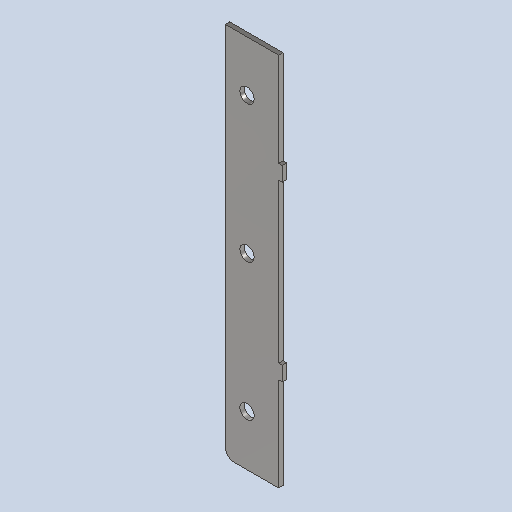
# Autodesk Inventor part: DMF-1214 Slot spoke 1
Saved by Autodesk Inventor 2026.2 (Build 302298000, 298)
## iProperties
Created: 2024-04-30
Part Number: DMF-1214 Slot spoke 1
Material: Stainless Steel
Document SubType Name: Sheet Metal
Designer: admin
Stock Number: DMF-1214
Mass: 30.2951 g
Surface Area: 223.238 cm^2
Volume: 30.2951 cm^3
Density: 8 g/cm^3
Flat Pattern Width: 3.95 cm
Flat Pattern Length: 26 cm
Flat Pattern Area: 102.7 cm^2
Sheet Metal Rule: Default
Sheet Metal Width: 39,500 mm
Sheet Metal Length: 260,000 mm
Sheet Metal Area: 10270,000 mm^2
Appearance: Semi-Polished
Author: pokla
Autodesk Inventor part; units mm, degrees
ref_plane "YZ Plane" through (0, 0, 0) normal (1, 0, 0) x (0, 1, 0)
ref_plane "XZ Plane" through (0, 0, 0) normal (0, 1, 0) x (-1, 0, 0)
ref_plane "XY Plane" through (0, 0, 0) normal (0, 0, 1) x (1, 0, 0)
sketch "Sketch1" plane through (0, 0, 0) normal (0, 0, 1) x (1, 0, 0)
  line L0 (0, 130) -> (0, -130)
  line L1 (0, -130) -> (-37, -130)
  line L2 (-37, -130) -> (-37, 130)
  line L3 (-37, 130) -> (0, 130)
  line L4 (-37, 0) -> (0, 0) construction
  line L5 (0, 65) -> (2.5, 65)
  line L6 (2.5, 65) -> (2.5, 55)
  line L7 (2.5, 55) -> (0, 55)
  line L8 (0, 55) -> (0, 65)
  line L9 (0, -55) -> (2.5, -55)
  line L10 (2.5, -55) -> (2.5, -65)
  line L11 (2.5, -65) -> (0, -65)
  line L12 (0, -65) -> (0, -55)
  circle A0 centre (-22, 95) radius 5
  circle A1 centre (-22, 0) radius 5
  circle A2 centre (-22, -95) radius 5
  point P0 (2.5, -60)
  point P1 (2.5, 60)
  dimension "d106" = 37
  dimension "d107" = 260
  dimension "d108" = 2.5
  dimension "d109" = 10
  dimension "d110" = 120
  dimension "d112" = 10
  dimension "d113" = 190
  dimension "d114" = 15
  measures "d106" distance of L2.end L0.start
  measures "d107" distance of L1.end L2.end
  measures "d108" distance of L6.end L7.end
  measures "d109" distance of L5.end L6.end
  measures "d110" distance of point (2.5, -60) point (2.5, 60)
  measures "d112" diameter of A1
  measures "d113" distance of A2.centre A0.centre
  measures "d114" distance from line of L2 A1.centre
extrude "Plate1" add sketch "Sketch1" along normal mid plane 3
fillet "Corner Round2" radius 6 1 edges at (-37, -130, 0)
equation "\"d15\" = Thickness"
equation "\"BendRadius\" = Thickness"
equation "\"BendReliefWidth\" = Thickness"
equation "\"BendReliefDepth\" = 0.5 * Thickness"
equation "\"CornerReliefSize\" = 4 * Thickness"
equation "\"MinimumRemnant\" = 2 * Thickness"
equation "\"TransitionRadius\" = BendRadius"
equation "\"JacobiRadiusSize\" = BendRadius"
equation "\"GapSize\" = Thickness"
equation "\"Thickness\" = 3"
body "Solid1"
